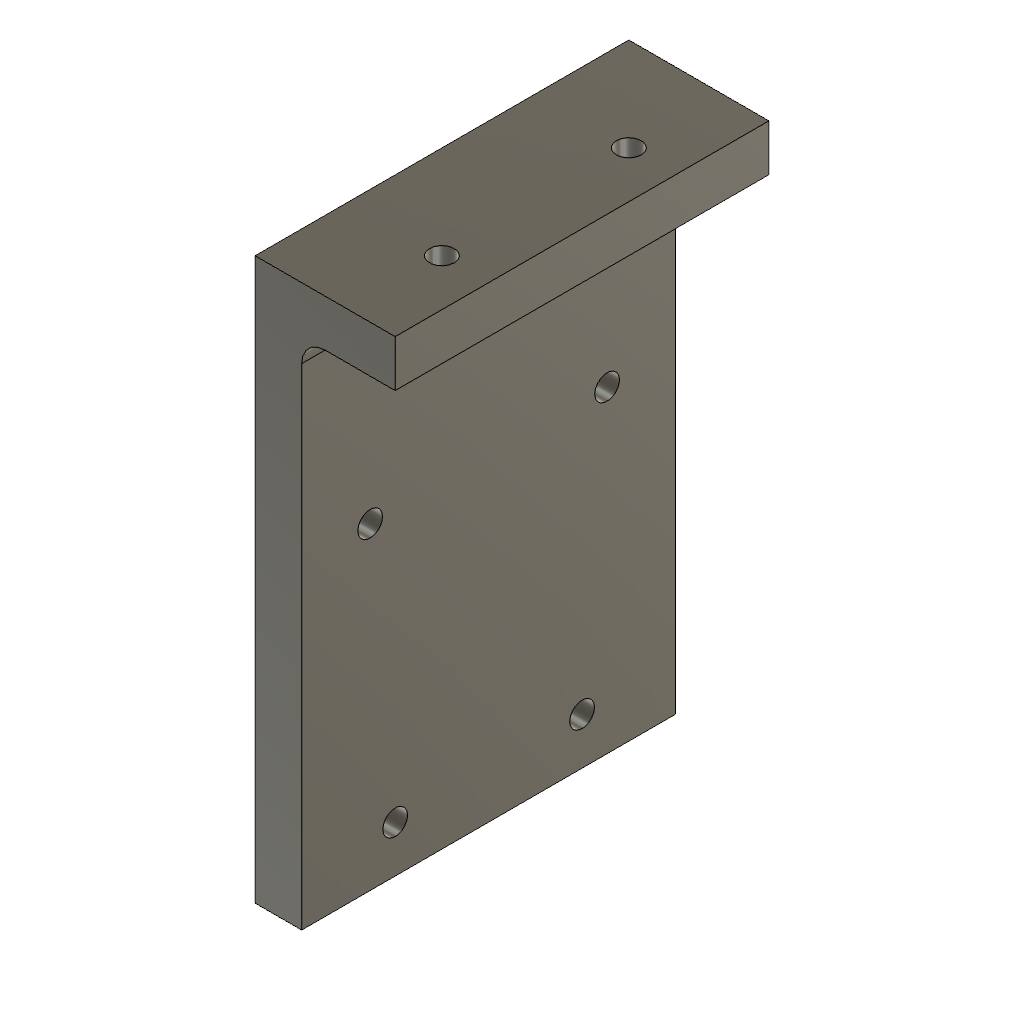
frame_plate_non_crank_side (Autodesk Fusion 360 design; units mm, degrees)
part number: 2026-10-05-15-48-32-500
Autodesk Fusion 360 part; units mm, degrees
sketch "Sketch1" plane through (0, 0, 0) normal (0, 1, 0) x (1, 0, 0)
  line L0 (0, 0) -> (40, 0)
  line L1 (40, 0) -> (40, -10)
  line L2 (40, -10) -> (10, -10)
  line L3 (10, -10) -> (10, -195)
  line L4 (10, -195) -> (30, -195)
  line L5 (30, -195) -> (30, -205)
  line L6 (30, -205) -> (0, -205)
  line L7 (0, -205) -> (0, 0)
  line L8 (0, -85) -> (10, -85)
  dimension "d1" = 40
  dimension "d2" = 10
  dimension "d3" = 185
  dimension "d4" = 20
  dimension "d5" = 10
  dimension "d6" = 30
  dimension "d25" = 85
  constraint coincident L0.start L7.end
  constraint horizontal L0
  constraint perpendicular L0 L1
  constraint perpendicular L1 L2
  constraint perpendicular L2 L3
  constraint perpendicular L3 L4
  constraint perpendicular L4 L5
  constraint perpendicular L5 L6
  constraint perpendicular L0 L7
  constraint coincident L7 L8.start
  constraint coincident L3 L8.end
  constraint perpendicular L3 L8
  measures "d1" distance of L0.start L0.end
  measures "d2" distance of L0.end L1.end
  measures "d3" distance of L2.end L3.end
  measures "d4" distance of L3.end L4.end
  measures "d5" distance of L4.end L5.end
  measures "d6" distance of L1.end L2.end
  measures "d25" distance of L0 L8
extrude "Extrude1" add sketch "Sketch1" along normal blind 80 contours L3 L4 L5 L6 L7 L8
sketch "Sketch2" plane through (0, 0, 0) normal (-1, 0, 0) x (0, -1, 0)
  line L0 (0, 85) -> (0, 205)
  line L1 (0, 205) -> (-80, 205)
  line L2 (-80, 205) -> (-80, 85)
  line L3 (-80, 153) -> (0, 153) construction
  circle A0 centre (-65.35, 153) radius 2.65
  circle A1 centre (-14.65, 153) radius 2.65
  line L4 (-80, 85) -> (0, 85)
  line L5 (-80, 95) -> (0, 95) construction
  circle A2 centre (-60, 95) radius 2.65
  circle A3 centre (-20, 95) radius 2.65
  dimension "d10" = 5.3
  dimension "d11" = 5.3
  dimension "d12" = 50.7
  dimension "d13" = 14.65
  dimension "d26" = 52
  dimension "d27" = 10
  dimension "d28" = 5.3
  dimension "d29" = 5.3
  dimension "d30" = 20
  dimension "d31" = 20
  constraint coincident L2 L3.start
  constraint coincident L0 L3.end
  constraint perpendicular L0 L3
  constraint coincident L3 A0.centre
  constraint coincident L3 A1.centre
  constraint coincident L2 L5.start
  constraint coincident L0 L5.end
  constraint perpendicular L0 L5
  constraint coincident L5 A2.centre
  constraint coincident L5 A3.centre
  measures "d10" diameter of A0
  measures "d11" diameter of A1
  measures "d12" distance of A0.centre A1.centre
  measures "d13" distance of L3.start A0.centre
  measures "d26" distance of L1 L3
  measures "d27" distance of L4 L5
  measures "d28" diameter of A2
  measures "d29" diameter of A3
  measures "d30" distance of L2 A2.centre
  measures "d31" distance of L0 A3.centre
extrude "Extrude2" cut sketch "Sketch2" against normal blind 10 contours A0 | A1 | A2 | A3
sketch "Sketch3" plane through (0, 0, 205) normal (0, 0, 1) x (-1, 0, 0)
  line L0 (0, 0) -> (-30, 0)
  line L1 (-30, 0) -> (-30, -80)
  line L2 (-30, -80) -> (0, -80)
  line L3 (0, -80) -> (0, 0)
  line L4 (-20, -80) -> (-20, 0) construction
  circle A0 centre (-20, -60) radius 2.65
  circle A1 centre (-20, -20) radius 2.65
  dimension "d16" = 10
  dimension "d17" = 5.3
  dimension "d18" = 5.3
  dimension "d19" = 20
  dimension "d20" = 20
  constraint coincident L2 L4.start
  constraint coincident L0 L4.end
  constraint perpendicular L0 L4
  constraint coincident L4 A0.centre
  constraint coincident L4 A1.centre
  measures "d16" distance of L1.end L4
  measures "d17" diameter of A0
  measures "d18" diameter of A1
  measures "d19" distance of L0 A1.centre
  measures "d20" distance of L4.start A0.centre
extrude "Extrude3" cut sketch "Sketch3" against normal blind 10 contours A0 | A1
fillet "Fillet1" radius 5 1 edges at (10, 40, 195)
